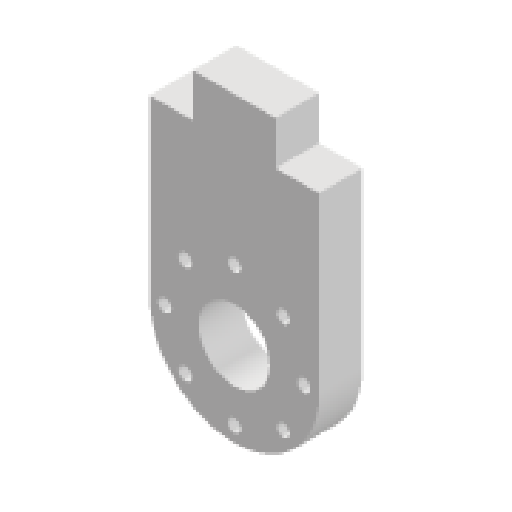
# Autodesk Inventor part: Pelv1
Saved by Autodesk Inventor 2025.2 (Build 292293000, 293)
## iProperties
Created: 2025-06-22
Part Number: Pelv1
Material: Generic
Document SubType Name: Modeling
Designer: ricoa
Density: 1 g/cm^3
Appearance: Default
Author: ricoa
Autodesk Inventor part; units mm, degrees
ref_plane "YZ Plane" through (0, 0, 0) normal (1, 0, 0) x (0, 1, 0)
ref_plane "XZ Plane" through (0, 0, 0) normal (0, 1, 0) x (-1, 0, 0)
ref_plane "XY Plane" through (0, 0, 0) normal (0, 0, 1) x (1, 0, 0)
sketch "Sketch1" plane through (0, 0, 0) normal (0, 0, 1) x (1, 0, 0)
  arc A0 (-9.75, 0) -> (9.75, 0) centre (0, 0) ccw
  circle A1 centre (-5.6569, 5.6569) radius 0.75 projected
  circle A2 centre (-8, 0) radius 0.75 projected
  circle A3 centre (-5.6569, -5.6569) radius 0.75 projected
  circle A4 centre (0, -8) radius 0.75 projected
  circle A5 centre (5.6569, -5.6569) radius 0.75 projected
  circle A6 centre (8, 0) radius 0.75 projected
  circle A7 centre (5.6569, 5.6569) radius 0.75 projected
  circle A8 centre (0, 8) radius 0.75 projected
  circle A9 centre (0, 0) radius 4.1
  line L0 (-9.75, 0) -> (-9.75, 20)
  line L1 (9.75, 0) -> (9.75, 20)
  line L2 (9.75, 20) -> (4.75, 20)
  line L3 (4.75, 20) -> (4.75, 25)
  line L4 (4.75, 25) -> (-4.75, 25)
  line L5 (-4.75, 25) -> (-4.75, 20)
  line L6 (-4.75, 20) -> (-9.75, 20)
  dimension "d2" = 20
  dimension "d4" = 8.2
  dimension "d5" = 9.75
  dimension "d6" = 5
  constraints: 14 end point, 4 perpendicular, 3 vertical, 2 centre point, 2 point on circle
  measures "d2" distance of L0.start L0.end
  measures "d4" diameter of A9
  measures "d5" distance of L0.start point (0, 0)
  measures "d6" distance between parallel lines of L6 L4
extrude "Extrusion1" add sketch "Sketch1" along normal blind 5
body "Solid1"
